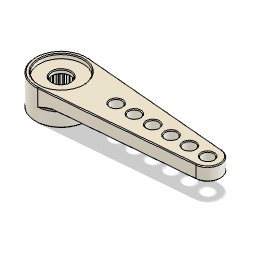
KST 0525.20 Alu Servoarm 20 mm 25T-5 v8 (Autodesk Fusion 360 design; units mm, degrees)
Autodesk Fusion 360 part; units mm, degrees
sketch "Skizze1" plane through (0, 0, 0) normal (0, 1, 0) x (1, 0, 0)
  circle A0 centre (0, 0) radius 3.5
  circle A1 centre (7.5, 0) radius 0.8
  line L0 (0, 0) -> (20, 0) construction
  circle A2 centre (10, 0) radius 0.8
  circle A3 centre (12.5, 0) radius 0.8
  circle A4 centre (15, 0) radius 0.8
  circle A5 centre (17.5, 0) radius 0.8
  circle A6 centre (20, 0) radius 0.8
  circle A7 centre (20, 0) radius 1.75
  line L1 (0.3062, 3.4866) -> (20.1531, 1.7433)
  line L2 (0.3062, -3.4866) -> (20.1531, -1.7433)
  circle A8 centre (0, 0) radius 3
  circle A9 centre (0, 0) radius 1.25
  circle A10 centre (0, 0) radius 2
  circle A11 centre (0, 0) radius 2.2
  dimension "d1" = 7
  dimension "d2" = 1.6
  dimension "d3" = 7.5
  dimension "d5" = 1.6
  dimension "d6" = 10
  dimension "d7" = 1.6
  dimension "d8" = 12.5
  dimension "d9" = 1.6
  dimension "d10" = 15
  dimension "d11" = 1.6
  dimension "d12" = 17.5
  dimension "d13" = 1.6
  dimension "d14" = 20
  dimension "d15" = 3.5
  dimension "d16" = 6
  dimension "d17" = 2.5
  dimension "d33" = 4
  dimension "d50" = 4.4
  constraint coincident A0.centre L0.start
  constraint horizontal L0
  constraint coincident A1.centre L0
  constraint coincident L0 A2.centre
  constraint coincident L0 A3.centre
  constraint coincident L0 A4.centre
  constraint coincident L0 A5.centre
  constraint coincident L0 A6.centre
  constraint concentric A6 A7
  constraint coincident A0 L1.start
  constraint coincident A7 L1.end
  constraint tangent A7 L1
  constraint tangent A0 L1
  constraint coincident A0 L2.start
  constraint coincident A7 L2.end
  constraint tangent A7 L2
  constraint tangent A0 L2
  constraint concentric A0 A8
  constraint coincident L0.end A6.centre
  constraint concentric A10 A11
  measures "d1" diameter of A0
  measures "d2" diameter of A1
  measures "d3" distance of A0.centre A1.centre
  measures "d5" diameter of A2
  measures "d6" distance of A0.centre A2.centre
  measures "d7" diameter of A3
  measures "d8" distance of A0.centre A3.centre
  measures "d9" diameter of A4
  measures "d10" distance of A0.centre A4.centre
  measures "d11" diameter of A5
  measures "d12" distance of A0.centre A5.centre
  measures "d13" diameter of A6
  measures "d14" distance of A0.centre L0.end
  measures "d15" diameter of A7
  measures "d16" diameter of A8
  measures "d17" diameter of A9
  measures "d33" diameter of A10
  measures "d50" diameter of A11
extrude "Extrusion1" add sketch "Skizze1" against normal blind 4.2 contours A0 | A8 | A10 | A11
extrude "Extrusion2" cut sketch "Skizze1" against normal blind 0.6 contours A8 | A10 | A11
extrude "Extrusion3" add sketch "Skizze1" against normal blind 1.8 contours A0 A5 A7 L1 L2 | A5 A7 picked at (18.6026, 0.2484)
sketch "Skizze2" plane through (0, 0, 0) normal (0, 1, 0) x (1, 0, 0)
  arc A0 (-1.9947, 0.9281) -> (-2.0277, 0.8534) centre (0, 0) ccw
  arc A1 (-0.8192, 2.0418) -> (-0.8944, 2.01) centre (0, 0) ccw
  arc A2 (2.1962, -0.1286) -> (2.1995, -0.0471) centre (0, 0) ccw
  arc A3 (1.6891, 1.4096) -> (1.6356, 1.4714) centre (0, 0) ccw
  arc A4 (-1.3012, 1.7739) -> (-1.3662, 1.7244) centre (0, 0) ccw
  arc A5 (-1.7521, 1.3305) -> (-1.9947, 0.9281) centre (0, 0) ccw construction
  arc A6 (-2.0277, 0.8534) -> (-2.1628, 0.4029) centre (0, 0) ccw construction
  arc A7 (2.1421, 0.5014) -> (1.9866, 0.9453) centre (0, 0) ccw construction
  arc A8 (-1.0511, -1.9327) -> (-0.9786, -1.9704) centre (0, 0) ccw
  arc A9 (-0.5374, -2.1334) -> (-0.4579, -2.1518) centre (0, 0) ccw
  arc A10 (-0.8944, 2.01) -> (-1.3012, 1.7739) centre (0, 0) ccw construction
  arc A11 (1.9866, 0.9453) -> (1.9501, 1.0184) centre (0, 0) ccw
  arc A12 (2.1995, -0.0471) -> (2.1592, 0.4216) centre (0, 0) ccw construction
  arc A13 (1.1393, -1.882) -> (1.5133, -1.5969) centre (0, 0) ccw construction
  arc A14 (-0.9786, -1.9704) -> (-0.5374, -2.1334) centre (0, 0) ccw construction
  arc A15 (-1.3662, 1.7244) -> (-1.7015, 1.3946) centre (0, 0) ccw construction
  arc A16 (-0.3664, 2.1693) -> (-0.8192, 2.0418) centre (0, 0) ccw construction
  arc A17 (-0.2857, 2.1814) -> (-0.3664, 2.1693) centre (0, 0) ccw
  arc A18 (2.1187, -0.5926) -> (2.1962, -0.1286) centre (0, 0) ccw construction
  arc A19 (-1.8524, -1.1868) -> (-1.8071, -1.2548) centre (0, 0) ccw
  arc A20 (-2.0894, -0.6889) -> (-2.0624, -0.7659) centre (0, 0) ccw
  arc A21 (-0.4579, -2.1518) -> (0.01, -2.2) centre (0, 0) ccw construction
  arc A22 (2.1592, 0.4216) -> (2.1421, 0.5014) centre (0, 0) ccw
  arc A23 (-1.7015, 1.3946) -> (-1.7521, 1.3305) centre (0, 0) ccw
  arc A24 (1.5715, -1.5396) -> (1.8628, -1.1705) centre (0, 0) ccw construction
  arc A25 (1.6356, 1.4714) -> (1.2854, 1.7854) centre (0, 0) ccw construction
  arc A26 (2.0952, -0.6708) -> (2.1187, -0.5926) centre (0, 0) ccw
  arc A27 (0.5568, -2.1284) -> (0.6354, -2.1062) centre (0, 0) ccw
  arc A28 (0.6354, -2.1062) -> (1.0686, -1.923) centre (0, 0) ccw construction
  arc A29 (0.1846, 2.1922) -> (-0.2857, 2.1814) centre (0, 0) ccw construction
  arc A30 (0.724, 2.0775) -> (0.2658, 2.1839) centre (0, 0) ccw construction
  arc A31 (1.2183, 1.8319) -> (0.8005, 2.0492) centre (0, 0) ccw construction
  arc A32 (1.8628, -1.1705) -> (1.9049, -1.1007) centre (0, 0) ccw
  arc A33 (-1.4383, -1.6647) -> (-1.0511, -1.9327) centre (0, 0) ccw construction
  arc A34 (0.2658, 2.1839) -> (0.1846, 2.1922) centre (0, 0) ccw
  arc A35 (1.2854, 1.7854) -> (1.2183, 1.8319) centre (0, 0) ccw
  arc A36 (0.8005, 2.0492) -> (0.724, 2.0775) centre (0, 0) ccw
  arc A37 (1.5133, -1.5969) -> (1.5715, -1.5396) centre (0, 0) ccw
  arc A38 (1.9501, 1.0184) -> (1.6891, 1.4096) centre (0, 0) ccw construction
  arc A39 (0.01, -2.2) -> (0.0917, -2.1981) centre (0, 0) ccw
  arc A40 (-2.1628, 0.4029) -> (-2.1763, 0.3224) centre (0, 0) ccw
  arc A41 (-2.1763, 0.3224) -> (-2.195, -0.1476) centre (0, 0) ccw construction
  arc A42 (-1.8071, -1.2548) -> (-1.4991, -1.6102) centre (0, 0) ccw construction
  arc A43 (-2.195, -0.1476) -> (-2.1881, -0.229) centre (0, 0) ccw
  arc A44 (-2.1881, -0.229) -> (-2.0894, -0.6889) centre (0, 0) ccw construction
  arc A45 (-2.0624, -0.7659) -> (-1.8524, -1.1868) centre (0, 0) ccw construction
  arc A46 (0.0917, -2.1981) -> (0.5568, -2.1284) centre (0, 0) ccw construction
  arc A47 (1.9049, -1.1007) -> (2.0952, -0.6708) centre (0, 0) ccw construction
  arc A48 (1.0686, -1.923) -> (1.1393, -1.882) centre (0, 0) ccw
  arc A49 (-1.4991, -1.6102) -> (-1.4383, -1.6647) centre (0, 0) ccw
  circle A50 centre (0, 0) radius 1.325 construction
  circle A51 centre (0, 0) radius 1.025
  circle A52 centre (0, 0) radius 1.325 construction
  circle A53 centre (0, 0) radius 2.5
  arc A54 (1.8628, -1.1705) -> (1.9049, -1.1007) centre (0, 0) ccw
  line L0 (1.9049, -1.1007) -> (2.2083, -1.1064)
  arc A55 (2.0952, -0.6708) -> (2.1187, -0.5926) centre (0, 0) ccw
  arc A56 (2.2083, -1.1064) -> (2.3035, -0.8916) centre (0, 0) ccw
  line L1 (2.0096, -1.4362) -> (1.8628, -1.1705)
  arc A57 (2.1592, 0.4216) -> (2.1421, 0.5014) centre (0, 0) ccw
  line L2 (-0.3664, 2.1693) -> (-0.5554, 2.4067)
  line L3 (-0.8944, 2.01) -> (-1.1365, 2.193)
  arc A58 (2.4682, 0.0946) -> (2.4481, 0.3284) centre (0, 0) ccw
  arc A59 (1.864, -1.6206) -> (2.0096, -1.4362) centre (0, 0) ccw
  line L4 (2.4528, -0.2907) -> (2.1962, -0.1286)
  arc A60 (-0.5554, 2.4067) -> (-0.7813, 2.3432) centre (0, 0) ccw
  arc A61 (-0.8192, 2.0418) -> (-0.8944, 2.01) centre (0, 0) ccw
  line L5 (-0.7813, 2.3432) -> (-0.8192, 2.0418)
  line L6 (2.4481, 0.3284) -> (2.1592, 0.4216)
  line L7 (1.5598, 1.9152) -> (1.2854, 1.7854)
  line L8 (2.2895, 0.9269) -> (1.9866, 0.9453)
  arc A62 (1.2854, 1.7854) -> (1.2183, 1.8319) centre (0, 0) ccw
  line L9 (1.9501, 1.0184) -> (2.1173, 1.272)
  arc A63 (2.3671, 0.7054) -> (2.2895, 0.9269) centre (0, 0) ccw
  line L10 (1.9871, 1.4671) -> (1.6891, 1.4096)
  arc A64 (1.6891, 1.4096) -> (1.6356, 1.4714) centre (0, 0) ccw
  arc A65 (1.9866, 0.9453) -> (1.9501, 1.0184) centre (0, 0) ccw
  arc A66 (1.7345, 1.7585) -> (1.5598, 1.9152) centre (0, 0) ccw
  line L11 (1.6356, 1.4714) -> (1.7345, 1.7585)
  arc A67 (2.1173, 1.272) -> (1.9871, 1.4671) centre (0, 0) ccw
  line L12 (1.2183, 1.8319) -> (1.2427, 2.1346)
  arc A68 (1.5133, -1.5969) -> (1.5715, -1.5396) centre (0, 0) ccw
  arc A69 (1.4024, -2.0333) -> (1.589, -1.891) centre (0, 0) ccw
  arc A70 (-0.2857, 2.1814) -> (-0.3664, 2.1693) centre (0, 0) ccw
  line L13 (0.724, 2.0775) -> (0.6727, 2.3766)
  arc A71 (0.8005, 2.0492) -> (0.724, 2.0775) centre (0, 0) ccw
  arc A72 (0.2658, 2.1839) -> (0.1846, 2.1922) centre (0, 0) ccw
  line L14 (1.0345, 2.2429) -> (0.8005, 2.0492)
  line L15 (0.4442, 2.4297) -> (0.2658, 2.1839)
  arc A73 (0.6727, 2.3766) -> (0.4442, 2.4297) centre (0, 0) ccw
  arc A74 (1.2427, 2.1346) -> (1.0345, 2.2429) centre (0, 0) ccw
  line L16 (0.1846, 2.1922) -> (0.0605, 2.4693)
  line L17 (1.1393, -1.882) -> (1.4024, -2.0333)
  arc A75 (-1.1365, 2.193) -> (-1.3395, 2.0753) centre (0, 0) ccw
  line L18 (-0.174, 2.4639) -> (-0.2857, 2.1814)
  line L19 (1.589, -1.891) -> (1.5133, -1.5969)
  arc A76 (0.0605, 2.4693) -> (-0.174, 2.4639) centre (0, 0) ccw
  line L20 (2.1995, -0.0471) -> (2.4682, 0.0946)
  line L21 (1.5715, -1.5396) -> (1.864, -1.6206)
  arc A77 (2.4142, -0.5222) -> (2.4528, -0.2907) centre (0, 0) ccw
  line L22 (2.3035, -0.8916) -> (2.0952, -0.6708)
  arc A78 (1.0686, -1.923) -> (1.1393, -1.882) centre (0, 0) ccw
  arc A79 (2.1962, -0.1286) -> (2.1995, -0.0471) centre (0, 0) ccw
  line L23 (2.1187, -0.5926) -> (2.4142, -0.5222)
  line L24 (2.1421, 0.5014) -> (2.3671, 0.7054)
  arc A80 (-1.5004, -1.9621) -> (-1.3074, -2.0956) centre (0, 0) ccw
  line L25 (-1.3074, -2.0956) -> (-1.0511, -1.9327)
  arc A81 (-1.0511, -1.9327) -> (-0.9786, -1.9704) centre (0, 0) ccw
  line L26 (-0.9786, -1.9704) -> (-0.9653, -2.2736)
  arc A82 (-0.9653, -2.2736) -> (-0.7452, -2.3549) centre (0, 0) ccw
  line L27 (-0.7452, -2.3549) -> (-0.5374, -2.1334)
  arc A83 (-0.5374, -2.1334) -> (-0.4579, -2.1518) centre (0, 0) ccw
  line L28 (-0.4579, -2.1518) -> (-0.3695, -2.4422)
  arc A84 (0.5568, -2.1284) -> (0.6354, -2.1062) centre (0, 0) ccw
  line L29 (1.0688, -2.2268) -> (1.0686, -1.923)
  line L30 (0.0917, -2.1981) -> (0.2494, -2.4574)
  arc A85 (0.01, -2.2) -> (0.0917, -2.1981) centre (0, 0) ccw
  line L31 (0.4815, -2.4226) -> (0.5568, -2.1284)
  line L32 (-0.1361, -2.4662) -> (0.01, -2.2)
  arc A86 (0.2494, -2.4574) -> (0.4815, -2.4226) centre (0, 0) ccw
  arc A87 (-0.3695, -2.4422) -> (-0.1361, -2.4662) centre (0, 0) ccw
  line L33 (0.6354, -2.1062) -> (0.8527, -2.3181)
  arc A88 (0.8527, -2.3181) -> (1.0688, -2.2268) centre (0, 0) ccw
  arc A89 (-1.3012, 1.7739) -> (-1.3662, 1.7244) centre (0, 0) ccw
  line L34 (-1.8135, 1.6769) -> (-1.7015, 1.3946)
  line L35 (-1.3662, 1.7244) -> (-1.6462, 1.8415)
  arc A90 (-1.6462, 1.8415) -> (-1.8135, 1.6769) centre (0, 0) ccw
  arc A91 (-1.7015, 1.3946) -> (-1.7521, 1.3305) centre (0, 0) ccw
  line L36 (-1.3395, 2.0753) -> (-1.3012, 1.7739)
  line L37 (-1.7521, 1.3305) -> (-2.0524, 1.3742)
  arc A92 (-2.0524, 1.3742) -> (-2.1736, 1.1733) centre (0, 0) ccw
  line L38 (-2.1736, 1.1733) -> (-1.9947, 0.9281)
  arc A93 (-1.9947, 0.9281) -> (-2.0277, 0.8534) centre (0, 0) ccw
  line L39 (-2.0277, 0.8534) -> (-2.3297, 0.8206)
  arc A94 (-2.3297, 0.8206) -> (-2.397, 0.5959) centre (0, 0) ccw
  line L40 (-2.397, 0.5959) -> (-2.1628, 0.4029)
  arc A95 (-2.1628, 0.4029) -> (-2.1763, 0.3224) centre (0, 0) ccw
  line L41 (-2.1763, 0.3224) -> (-2.4606, 0.2155)
  arc A96 (-2.4606, 0.2155) -> (-2.4699, -0.019) centre (0, 0) ccw
  line L42 (-2.4699, -0.019) -> (-2.195, -0.1476)
  arc A97 (-2.195, -0.1476) -> (-2.1881, -0.229) centre (0, 0) ccw
  line L43 (-2.1881, -0.229) -> (-2.4369, -0.4032)
  arc A98 (-2.4369, -0.4032) -> (-2.3876, -0.6326) centre (0, 0) ccw
  line L44 (-2.3876, -0.6326) -> (-2.0894, -0.6889)
  arc A99 (-2.0894, -0.6889) -> (-2.0624, -0.7659) centre (0, 0) ccw
  line L45 (-2.0624, -0.7659) -> (-2.26, -0.9966)
  arc A100 (-2.26, -0.9966) -> (-2.1553, -1.2065) centre (0, 0) ccw
  line L46 (-2.1553, -1.2065) -> (-1.8524, -1.1868)
  arc A101 (-1.8524, -1.1868) -> (-1.8071, -1.2548) centre (0, 0) ccw
  line L47 (-1.8071, -1.2548) -> (-1.9412, -1.5273)
  arc A102 (-1.9412, -1.5273) -> (-1.7875, -1.7046) centre (0, 0) ccw
  line L48 (-1.7875, -1.7046) -> (-1.4991, -1.6102)
  arc A103 (-1.4991, -1.6102) -> (-1.4383, -1.6647) centre (0, 0) ccw
  line L49 (-1.4383, -1.6647) -> (-1.5004, -1.9621)
  line L50 (-0.8944, 2.01) -> (-1.1365, 2.193)
  arc A104 (-1.1365, 2.193) -> (-1.3395, 2.0753) centre (0, 0) ccw
  line L51 (-1.3395, 2.0753) -> (-1.3012, 1.7739)
  line L52 (2.2241, -0.0623) -> (2.4937, 0.0798)
  arc A105 (2.4937, 0.0798) -> (2.4707, 0.3473) centre (0, 0) ccw
  line L53 (2.4707, 0.3473) -> (2.1809, 0.4409)
  arc A106 (2.1809, 0.4409) -> (2.1698, 0.4927) centre (0, 0) ccw
  line L54 (2.1698, 0.4927) -> (2.3955, 0.6975)
  arc A107 (2.3955, 0.6975) -> (2.3067, 0.9509) centre (0, 0) ccw
  line L55 (2.3067, 0.9509) -> (2.0027, 0.9694)
  arc A108 (2.0027, 0.9694) -> (1.979, 1.0169) centre (0, 0) ccw
  line L56 (1.979, 1.0169) -> (2.1468, 1.2713)
  arc A109 (2.1468, 1.2713) -> (1.9978, 1.4947) centre (0, 0) ccw
  line L57 (1.9978, 1.4947) -> (1.6987, 1.437)
  arc A110 (1.6987, 1.437) -> (1.664, 1.4771) centre (0, 0) ccw
  line L58 (1.664, 1.4771) -> (1.7632, 1.7652)
  arc A111 (1.7632, 1.7652) -> (1.5633, 1.9445) centre (0, 0) ccw
  line L59 (1.5633, 1.9445) -> (1.288, 1.8143)
  arc A112 (1.288, 1.8143) -> (1.2444, 1.8445) centre (0, 0) ccw
  line L60 (1.2444, 1.8445) -> (1.2688, 2.1483)
  arc A113 (1.2688, 2.1483) -> (1.0306, 2.2722) centre (0, 0) ccw
  line L61 (1.0306, 2.2722) -> (0.7959, 2.0778)
  arc A114 (0.7959, 2.0778) -> (0.7461, 2.0962) centre (0, 0) ccw
  line L62 (0.7461, 2.0962) -> (0.6947, 2.3963)
  arc A115 (0.6947, 2.3963) -> (0.4331, 2.4571) centre (0, 0) ccw
  line L63 (0.4331, 2.4571) -> (0.2542, 2.2104)
  arc A116 (0.2542, 2.2104) -> (0.2014, 2.2159) centre (0, 0) ccw
  line L64 (0.2014, 2.2159) -> (0.0769, 2.4938)
  arc A117 (0.0769, 2.4938) -> (-0.1915, 2.4876) centre (0, 0) ccw
  line L65 (-0.1915, 2.4876) -> (-0.3035, 2.2042)
  arc A118 (-0.3035, 2.2042) -> (-0.356, 2.1963) centre (0, 0) ccw
  line L66 (-0.356, 2.1963) -> (-0.5457, 2.4346)
  arc A119 (-0.5457, 2.4346) -> (-0.8042, 2.3619) centre (0, 0) ccw
  line L67 (-0.8042, 2.3619) -> (-0.8422, 2.0595)
  arc A120 (-0.8422, 2.0595) -> (-0.891, 2.0388) centre (0, 0) ccw
  line L68 (-0.891, 2.0388) -> (-1.134, 2.2224)
  arc A121 (-1.134, 2.2224) -> (-1.3663, 2.0877) centre (0, 0) ccw
  line L69 (-1.3663, 2.0877) -> (-1.3279, 1.7853)
  arc A122 (-1.3279, 1.7853) -> (-1.3701, 1.7532) centre (0, 0) ccw
  line L70 (-1.3701, 1.7532) -> (-1.651, 1.8706)
  arc A123 (-1.651, 1.8706) -> (-1.8425, 1.6823) centre (0, 0) ccw
  line L71 (-1.8425, 1.6823) -> (-1.7301, 1.399)
  arc A124 (-1.7301, 1.399) -> (-1.763, 1.3573) centre (0, 0) ccw
  line L72 (-1.763, 1.3573) -> (-2.0644, 1.4012)
  arc A125 (-2.0644, 1.4012) -> (-2.203, 1.1712) centre (0, 0) ccw
  line L73 (-2.203, 1.1712) -> (-2.0235, 0.9252)
  arc A126 (-2.0235, 0.9252) -> (-2.045, 0.8767) centre (0, 0) ccw
  line L74 (-2.045, 0.8767) -> (-2.348, 0.8438)
  arc A127 (-2.348, 0.8438) -> (-2.4251, 0.5866) centre (0, 0) ccw
  line L75 (-2.4251, 0.5866) -> (-2.19, 0.3929)
  arc A128 (-2.19, 0.3929) -> (-2.1988, 0.3406) centre (0, 0) ccw
  line L76 (-2.1988, 0.3406) -> (-2.4841, 0.2334)
  arc A129 (-2.4841, 0.2334) -> (-2.4948, -0.0349) centre (0, 0) ccw
  line L77 (-2.4948, -0.0349) -> (-2.2189, -0.164)
  arc A130 (-2.2189, -0.164) -> (-2.2144, -0.2169) centre (0, 0) ccw
  line L78 (-2.2144, -0.2169) -> (-2.4641, -0.3917)
  arc A131 (-2.4641, -0.3917) -> (-2.4077, -0.6543) centre (0, 0) ccw
  line L79 (-2.4077, -0.6543) -> (-2.1084, -0.7107)
  arc A132 (-2.1084, -0.7107) -> (-2.0909, -0.7608) centre (0, 0) ccw
  line L80 (-2.0909, -0.7608) -> (-2.2892, -0.9922)
  arc A133 (-2.2892, -0.9922) -> (-2.1693, -1.2325) centre (0, 0) ccw
  line L81 (-2.1693, -1.2325) -> (-1.8654, -1.2127)
  arc A134 (-1.8654, -1.2127) -> (-1.836, -1.2569) centre (0, 0) ccw
  line L82 (-1.836, -1.2569) -> (-1.9706, -1.5303)
  arc A135 (-1.9706, -1.5303) -> (-1.7947, -1.7333) centre (0, 0) ccw
  line L83 (-1.7947, -1.7333) -> (-1.5052, -1.6386)
  arc A136 (-1.5052, -1.6386) -> (-1.4657, -1.674) centre (0, 0) ccw
  line L84 (-1.4657, -1.674) -> (-1.5281, -1.9723)
  arc A137 (-1.5281, -1.9723) -> (-1.3072, -2.1251) centre (0, 0) ccw
  line L85 (-1.3072, -2.1251) -> (-1.05, -1.9616)
  arc A138 (-1.05, -1.9616) -> (-1.003, -1.9861) centre (0, 0) ccw
  line L86 (-1.003, -1.9861) -> (-0.9896, -2.2904)
  arc A139 (-0.9896, -2.2904) -> (-0.7377, -2.3835) centre (0, 0) ccw
  line L87 (-0.7377, -2.3835) -> (-0.5292, -2.1612)
  arc A140 (-0.5292, -2.1612) -> (-0.4775, -2.1732) centre (0, 0) ccw
  line L88 (-0.4775, -2.1732) -> (-0.3889, -2.4645)
  arc A141 (-0.3889, -2.4645) -> (-0.1218, -2.492) centre (0, 0) ccw
  line L89 (-0.1218, -2.492) -> (0.0249, -2.2249)
  arc A142 (0.0249, -2.2249) -> (0.0779, -2.2236) centre (0, 0) ccw
  line L90 (0.0779, -2.2236) -> (0.2362, -2.4838)
  arc A143 (0.2362, -2.4838) -> (0.5018, -2.444) centre (0, 0) ccw
  line L91 (0.5018, -2.444) -> (0.5774, -2.1488)
  arc A144 (0.5774, -2.1488) -> (0.6285, -2.1344) centre (0, 0) ccw
  line L92 (0.6285, -2.1344) -> (0.8465, -2.347)
  arc A145 (0.8465, -2.347) -> (1.0938, -2.2424) centre (0, 0) ccw
  line L93 (1.0938, -2.2424) -> (1.0936, -1.9377)
  arc A146 (1.0936, -1.9377) -> (1.1395, -1.911) centre (0, 0) ccw
  line L94 (1.1395, -1.911) -> (1.4036, -2.0628)
  arc A147 (1.4036, -2.0628) -> (1.6171, -1.9) centre (0, 0) ccw
  line L95 (1.6171, -1.9) -> (1.5412, -1.6048)
  arc A148 (1.5412, -1.6048) -> (1.579, -1.5676) centre (0, 0) ccw
  line L96 (1.579, -1.5676) -> (1.8725, -1.6489)
  arc A149 (1.8725, -1.6489) -> (2.039, -1.4378) centre (0, 0) ccw
  line L97 (2.039, -1.4378) -> (1.8918, -1.1713)
  arc A150 (1.8918, -1.1713) -> (1.9191, -1.126) centre (0, 0) ccw
  line L98 (1.9191, -1.126) -> (2.2236, -1.1317)
  arc A151 (2.2236, -1.1317) -> (2.3324, -0.8859) centre (0, 0) ccw
  line L99 (2.3324, -0.8859) -> (2.1235, -0.6643)
  arc A152 (2.1235, -0.6643) -> (2.1387, -0.6135) centre (0, 0) ccw
  line L100 (2.1387, -0.6135) -> (2.4352, -0.5429)
  arc A153 (2.4352, -0.5429) -> (2.4795, -0.278) centre (0, 0) ccw
  line L101 (2.4795, -0.278) -> (2.222, -0.1154)
  arc A154 (2.222, -0.1154) -> (2.2241, -0.0623) centre (0, 0) ccw
  dimension "d40" = 0
  dimension "d41" = 0.025
  dimension "d48" = 2.2
  dimension "d49" = 5
  constraint coincident A0.centre A1.centre
  measures "d48" radius of A28
  measures "d49" diameter of A53
extrude "Extrusion6" cut sketch "Skizze1" along normal blind 0.5 from surface at -4.2 contours A9 | A10 | A11
chamfer "Fase3" distance 0.5 angle 45 1 edges at (-2.0511, -4.2, 0.7956)
extrude "Extrusion5" cut sketch "Skizze2" along normal blind 3 from surface at -4.2 contours A0 A1 A2 A3 A4 A8 A9 A11 A17 A19 A20 A22 A23 A26 A27 A32 A34 A35 A36 A37 A39 A40 A43 A48 A49 A54 L0 A55 A56 L1 A57 L2 L3 A58 A59 L4 A60 A61 L5 L6 L7 L8 A62 L9 A63 L10 A64 A65 A66 L11 A67 L12 A68 A69 A70 L13 A71 A72 L14 L15 A73 A74 L16 L17 A75 L18 L19 A76 L20 L21 A77 L22 A78 A79 L23 L24 A80 L25 A81 L26 A82 L27 A83 L28 A84 L29 L30 A85 L31 L32 A86 A87 L33 A88 A89 L34 L35 A90 A91 L36 L37 A92 L38 A93 L39 A94 L40 A95 L41 A96 L42 A97 L43 A98 L44 A99 L45 A100 L46 A101 L47 A102 L48 A103 L49 L50 A104 L51 | L52 A105 L53 A106 L54 A107 L55 A108 L56 A109 L57 A110 L58 A111 L59 A112 L60 A113 L61 A114 L62 A115 L63 A116 L64 A117 L65 A118 L66 A119 L67 A120 L68 A121 L69 A122 L70 A123 L71 A124 L72 A125 L73 A126 L74 A127 L75 A128 L76 A129 L77 A130 L78 A131 L79 A132 L80 A133 L81 A134 L82 A135 L83 A136 L84 A137 L85 A138 L86 A139 L87 A140 L88 A141 L89 A142 L90 A143 L91 A144 L92 A145 L93 A146 L94 A147 L95 A148 L96 A149 L97 A150 L98 A151 L99 A152 L100 A153 L101 A154
chamfer "Fase1" distance 0.1 angle 45 8 edges at (6.7541, 0, -0.2893) (9.2541, 0, -0.2893) (11.7541, 0, -0.2893) (14.2541, 0, -0.2893) (16.7541, 0, -0.2893) (19.2541, 0, -0.2893) (-2.797, 0, -1.0848) (-1.1654, -0.6, 0.452)
chamfer "Fase1" distance 0.1 angle 45 6 edges at (6.7541, -1.8, 0.2893) (9.2541, -1.8, 0.2893) (11.7541, -1.8, 0.2893) (14.2541, -1.8, 0.2893) (16.7541, -1.8, 0.2893) (19.2541, -1.8, 0.2893)
chamfer "Fase1" distance 0.1 angle 45 1 edges at (-1.1654, -1.2, -0.452)
fillet "Abrundung2" radius 0.5 1 edges at (3.5, -1.8, 0)
fillet "Abrundung4" radius 0.1 10 edges at (1.2555, -1.9659, -3.4032) (11.1942, -1.8, -2.5302) (21.75, -1.8, 0) (11.1942, -1.8, 2.5302) (1.2555, -1.9659, 3.4032) (-3.2631, -4.2, -1.2657) (10.2297, 0, -2.6149) (-3.5, 0, 0) (10.2297, 0, 2.6149) (21.75, 0, 0)
equation "d5 = d2"
equation "d7 = d2"
equation "d9 = d2"
equation "d11 = d2"
equation "d13 = d2"
named bodies: "KST 0525.20 Alu Servoarm 20 mm, 25T-5"
